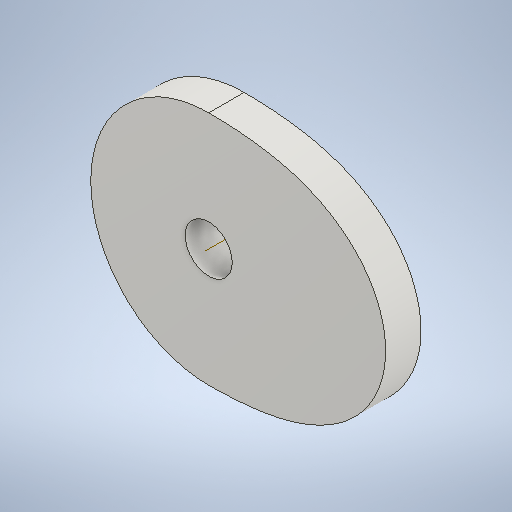
# Autodesk Inventor part: Disc Cam
Saved by Autodesk Inventor 2025.2 (Build 292293000, 293)
## iProperties
CustomPartVersion: 1
Created: 2025-05-17
Part Number: Disc Cam
Material: Stainless Steel, Austenitic
Document SubType Name: Modeling
Designer: laura
Manufacturer: Standard
Standards Organization: Custom
Density: 1 g/cm^3
Appearance: Steel
Author: laura
Autodesk Inventor part; units mm, degrees
ref_plane "YZ Plane" through (0, 0, 0) normal (1, 0, 0) x (0, 1, 0)
ref_plane "XZ Plane" through (0, 0, 0) normal (0, 1, 0) x (-1, 0, 0)
ref_plane "XY Plane" through (0, 0, 0) normal (0, 0, 1) x (1, 0, 0)
sketch "Main Sketch" plane through (0, 0, 0) normal (0, 0, 1) x (1, 0, 0)
  spline S0 degree 5 poles (0, 20) (0.6326, 20.0057) (1.7614, 19.9909) (3.6572, 19.926) (5.7554, 19.7958) (8.6547, 19.4791) (11.2542, 19.0418) (13.9549, 18.399) (16.5402, 17.5485) (19.0203, 16.466) (21.3468, 15.138) (23.4867, 13.5594) (25.3942, 11.7374) (27.0267, 9.6911) (28.3433, 7.4508) (29.3099, 5.0565) (29.9005, 2.5555) (30.0991, 0) (29.9005, -2.5555) (29.3099, -5.0565) (28.3433, -7.4508) (27.0267, -9.6911) (25.3942, -11.7374) (23.4867, -13.5594) (21.3469, -15.138) (19.0202, -16.466) (16.5405, -17.5485) (13.9543, -18.3991) (11.2557, -19.0416) (8.5572, -19.4952) (5.7131, -19.7988) (3.1656, -19.9557) (0.0572, -20.0386) (-1.8689, -19.9744) (-4.1485, -19.6275) (-6.1694, -19.0801) (-8.1632, -18.3204) (-10.0248, -17.3683) (-11.7891, -16.2246) (-13.4189, -14.9038) (-14.9039, -13.4193) (-16.2247, -11.788) (-17.3681, -10.0275) (-18.3211, -8.1571) (-19.0734, -6.1973) (-19.6167, -4.1697) (-19.9451, -2.0963) (-20.0549, 0) (-19.9451, 2.0963) (-19.6167, 4.1697) (-19.0734, 6.1973) (-18.321, 8.1571) (-17.3681, 10.0275) (-16.2246, 11.788) (-14.904, 13.4193) (-13.4187, 14.9038) (-11.7896, 16.2246) (-10.0237, 17.3684) (-8.1658, 18.3202) (-6.2566, 19.0451) (-4.2949, 19.5927) (-2.5254, 19.8752) (-1.3868, 19.9693) (-0.541, 19.9952) (0, 20) knots 0 0 0 0 0 0 0.021929 0.036486 0.054627 0.072667 0.090601 0.108434 0.126174 0.143831 0.161411 0.178916 0.196351 0.213719 0.231031 0.248301 0.26555 0.282798 0.300068 0.31738 0.334748 0.352183 0.369688 0.387268 0.404925 0.422665 0.440498 0.458432 0.476472 0.494613 0.512296 0.529496 0.546191 0.562359 0.577989 0.593619 0.609249 0.624879 0.640509 0.656139 0.671769 0.687399 0.703029 0.718659 0.734289 0.749919 0.76555 0.78118 0.79681 0.81244 0.82807 0.8437 0.85933 0.87496 0.89059 0.90622 0.92185 0.93748 0.95311 0.96874 0.981244 1 1 1 1 1 1
  point P0 (5.7281, 19.7665)
  point P1 (8.537, 19.4555)
  point P2 (11.2862, 18.9877)
  point P3 (13.9607, 18.3375)
  point P4 (16.5425, 17.4795)
  point P5 (19.007, 16.3922)
  point P6 (21.3218, 15.0613)
  point P7 (23.4478, 13.4825)
  point P8 (25.3418, 11.6636)
  point P9 (26.9606, 9.6241)
  point P10 (28.2644, 7.395)
  point P11 (29.2204, 5.0163)
  point P12 (29.8038, 2.5344)
  point P13 (30, 0)
  point P14 (29.8038, -2.5344)
  point P15 (29.2204, -5.0163)
  point P16 (28.2644, -7.395)
  point P17 (26.9606, -9.6241)
  point P18 (25.3418, -11.6636)
  point P19 (23.4478, -13.4825)
  point P20 (21.3218, -15.0613)
  point P21 (19.007, -16.3922)
  point P22 (16.5425, -17.4795)
  point P23 (13.9607, -18.3375)
  point P24 (11.2862, -18.9877)
  point P25 (8.537, -19.4555)
  point P26 (5.7281, -19.7665)
  point P27 (2.8758, -19.943)
  point P28 (0, -20)
  point P29 (-2.0906, -19.8904)
  point P30 (-4.1582, -19.563)
  point P31 (-6.1803, -19.0211)
  point P32 (-8.1347, -18.2709)
  point P33 (-10, -17.3205)
  point P34 (-11.7557, -16.1803)
  point P35 (-13.3826, -14.8629)
  point P36 (-14.8629, -13.3826)
  point P37 (-16.1803, -11.7557)
  point P38 (-17.3205, -10)
  point P39 (-18.2709, -8.1347)
  point P40 (-19.0211, -6.1803)
  point P41 (-19.563, -4.1582)
  point P42 (-19.8904, -2.0906)
  point P43 (-20, 0)
  point P44 (-19.8904, 2.0906)
  point P45 (-19.563, 4.1582)
  point P46 (-19.0211, 6.1803)
  point P47 (-18.2709, 8.1347)
  point P48 (-17.3205, 10)
  point P49 (-16.1803, 11.7557)
  point P50 (-14.8629, 13.3826)
  point P51 (-13.3826, 14.8629)
  point P52 (-11.7557, 16.1803)
  point P53 (-10, 17.3205)
  point P54 (-8.1347, 18.2709)
  point P55 (-6.1803, 19.0211)
  point P56 (-4.1582, 19.563)
  point P57 (-2.0906, 19.8904)
  constraints: 60 other
extrude "Cam" add sketch "Main Sketch" along normal blind 6
sketch "Sketch2" plane through (0, 0, 6) normal (0, 0, 1) x (1, 0, 0)
  circle A0 centre (0, 0) radius 4
  dimension "d4" = 8
  constraints: 1 centre point, 1 coincident
  measures "d4" diameter of A0
extrude "Extrusion2" cut sketch "Sketch2" against normal through all
body "Solid1"
